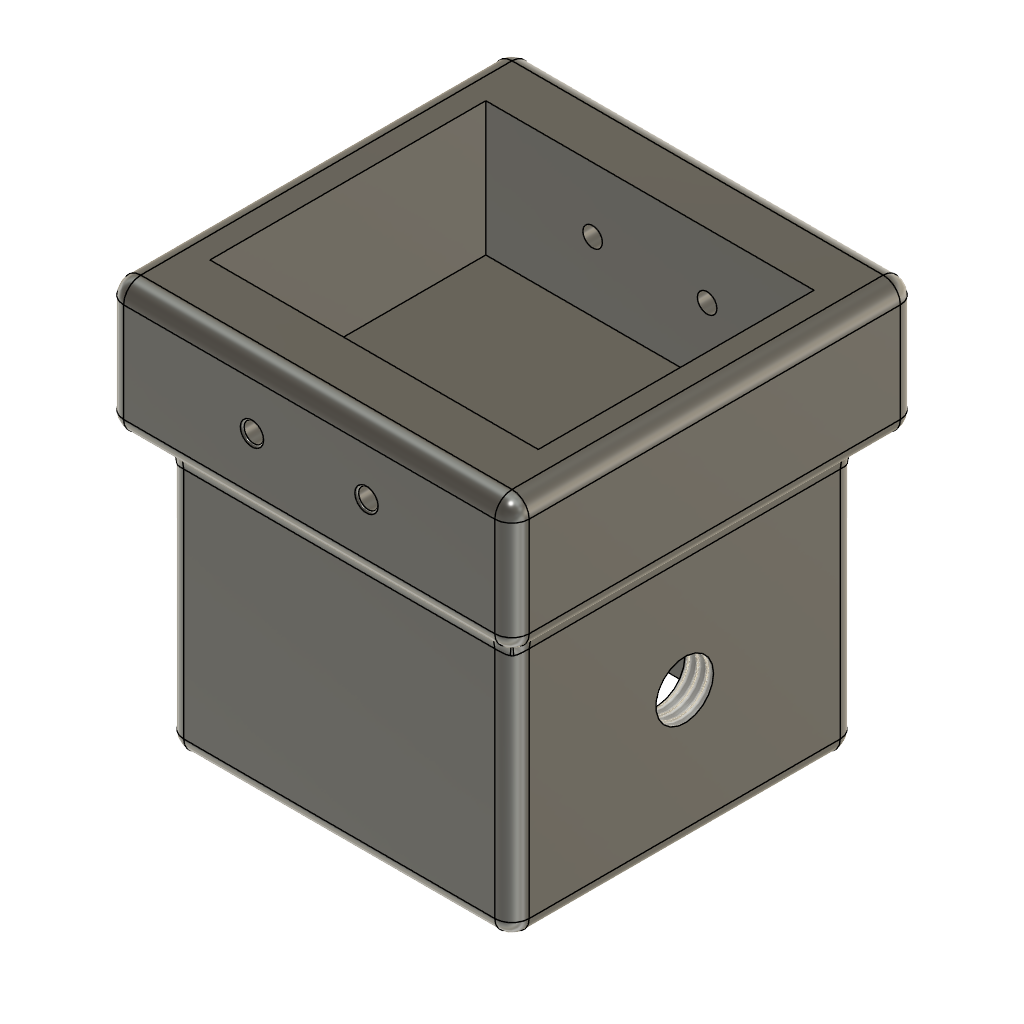
Arm Assembly (Autodesk Fusion 360 archive; units mm, degrees)
design "LongAluEndJoint"
part number: 2026-10-23-13-15-02-691
Autodesk Fusion 360 part; units mm, degrees
sketch "Sketch1" plane through (0, 0, 0) normal (0, 0, 1) x (1, 0, 0)
  line L0 (15.1, -15.1) -> (-15.1, -15.1)
  line L1 (-15.1, -15.1) -> (-15.1, 15.1)
  line L2 (-15.1, 15.1) -> (15.1, 15.1)
  line L3 (15.1, 15.1) -> (15.1, -15.1)
  line L4 (15.1, -15.1) -> (-15.1, 15.1) construction
  line L5 (-15.1, -15.1) -> (15.1, 15.1) construction
  line L6 (-18.1, -18.1) -> (18.1, -18.1)
  line L7 (18.1, -18.1) -> (18.1, 18.1)
  line L8 (18.1, 18.1) -> (-18.1, 18.1)
  line L9 (-18.1, 18.1) -> (-18.1, -18.1)
  line L10 (-18.1, -18.1) -> (18.1, 18.1) construction
  line L11 (18.1, -18.1) -> (-18.1, 18.1) construction
  dimension "d1" = 30.2
  dimension "d2" = 30.2
  dimension "d3" = 36.2
  dimension "d4" = 36.2
  constraint horizontal L0
  constraint perpendicular L0 L1
  constraint parallel L0 L2
  constraint parallel L1 L3
  constraint coincident L4 origin
  constraint coincident L5 origin
  constraint horizontal L6
  constraint perpendicular L6 L7
  constraint parallel L6 L8
  constraint parallel L7 L9
  constraint coincident L10 origin
  constraint coincident L11 origin
  measures "d1" distance of L1.end L2.end
  measures "d2" distance of L0.end L1.end
  measures "d3" distance of L7.end L8.end
  measures "d4" distance of L6.end L7.end
extrude "Extrude1" add sketch "Sketch1" along normal blind 24
sketch "Sketch2" plane through (0, 0, 24) normal (0, 0, 1) x (-1, 0, 0)
  line L0 (15.1, -15.1) -> (-15.1, -15.1)
  line L1 (-15.1, -15.1) -> (-15.1, 15.1)
  line L2 (-15.1, 15.1) -> (15.1, 15.1)
  line L3 (15.1, 15.1) -> (15.1, -15.1)
  line L4 (18.1, -18.1) -> (18.1, 18.1)
  line L5 (18.1, 18.1) -> (-18.1, 18.1)
  line L6 (-18.1, 18.1) -> (-18.1, -18.1)
  line L7 (-18.1, -18.1) -> (18.1, -18.1)
  line L8 (18.1, 18.1) -> (-18.1, 18.1)
  line L9 (-18.1, 18.1) -> (-18.1, -18.1)
  line L10 (-18.1, -18.1) -> (18.1, -18.1)
  line L11 (18.1, -18.1) -> (18.1, 18.1)
  line L12 (18.1, 18.1) -> (-18.1, -18.1) construction
  line L13 (-18.1, 18.1) -> (18.1, -18.1) construction
  dimension "d7" = 36.2
  dimension "d8" = 36.2
  constraint horizontal L8
  constraint perpendicular L8 L9
  constraint parallel L8 L10
  constraint parallel L9 L11
  constraint coincident L12 origin
  constraint coincident L13 origin
  measures "d7" distance of L6.end L4.start
  measures "d8" distance of L5.end L6.end
extrude "Extrude2" add sketch "Sketch2" along normal blind 5 contours L0 L1 L2 L3 | L4 L5 L6 L7 L8 L9 L10 L11
sketch "Sketch3" plane through (0, 0, 29) normal (0, 0, 1) x (-1, 0, 0)
  line L0 (18.1, -18.1) -> (18.1, 18.1)
  line L1 (18.1, 18.1) -> (-18.1, 18.1)
  line L2 (-18.1, 18.1) -> (-18.1, -18.1)
  line L3 (-18.1, -18.1) -> (18.1, -18.1)
  line L4 (-17.2, 14.45) -> (17.2, 14.45)
  line L5 (17.2, 14.45) -> (17.2, -14.45)
  line L6 (17.2, -14.45) -> (-17.2, -14.45)
  line L7 (-17.2, -14.45) -> (-17.2, 14.45)
  line L8 (-17.2, 14.45) -> (17.2, -14.45) construction
  line L9 (17.2, 14.45) -> (-17.2, -14.45) construction
  line L10 (-21.25, 21.25) -> (21.25, 21.25)
  line L11 (21.25, 21.25) -> (21.25, -21.25)
  line L12 (21.25, -21.25) -> (-21.25, -21.25)
  line L13 (-21.25, -21.25) -> (-21.25, 21.25)
  line L14 (-21.25, 21.25) -> (21.25, -21.25) construction
  line L15 (21.25, 21.25) -> (-21.25, -21.25) construction
  dimension "d11" = 34.4
  dimension "d12" = 28.9
  dimension "d13" = 42.5
  dimension "d14" = 42.5
  constraint horizontal L4
  constraint perpendicular L4 L5
  constraint parallel L4 L6
  constraint parallel L5 L7
  constraint coincident L8 origin
  constraint coincident L9 origin
  constraint horizontal L10
  constraint perpendicular L10 L11
  constraint parallel L10 L12
  constraint parallel L11 L13
  constraint coincident L14 origin
  constraint coincident L15 origin
  measures "d11" distance of L5.end L6.end
  measures "d12" distance of L4.end L5.end
  measures "d13" distance of L11.end L12.end
  measures "d14" distance of L10.end L11.end
extrude "Extrude3" add sketch "Sketch3" along normal blind 14 contours L0 L1 L2 L3 | L10 L11 L12 L13
fillet "Fillet1" radius 1.8 20 edges at (-21.25, -21.25, 36) (0, -21.25, 29) (-21.25, 0, 29) (21.25, -21.25, 36) (18.1, -18.1, 14.5) (-18.1, -18.1, 14.5) (-18.1, 18.1, 14.5) (18.1, 18.1, 14.5) (21.25, 0, 29) (0, 21.25, 29) (21.25, 21.25, 36) (-21.25, 21.25, 36) (-21.25, 0, 43) (0, 21.25, 43) (21.25, 0, 43) (0, -21.25, 43) (-18.1, 0, 0) (0, -18.1, 0) (18.1, 0, 0) (0, 18.1, 0)
sketch "Sketch4" plane through (0, -14.45, 0) normal (0, 1, 0) x (-1, 0, 0)
  line L0 (-17.2, 29) -> (17.2, 29)
  line L1 (17.2, 29) -> (17.2, 43)
  line L2 (17.2, 43) -> (-17.2, 43)
  line L3 (-17.2, 43) -> (-17.2, 29)
  circle A0 centre (-6, 36.25) radius 1.025
  line L4 (0, 29) -> (0, 43)
  circle A1 centre (6, 36.25) radius 1.025
  dimension "d21" = 2.05
  dimension "d22" = 7.25
  dimension "d23" = 6
  constraint midpoint L0 L4.start
  constraint midpoint L2 L4.end
  constraint symmetric A0 L4 A1
  measures "d21" diameter of A0
  measures "d22" distance of L0 A0.centre
  measures "d23" distance of A0.centre L4
extrude "Extrude4" cut sketch "Sketch4" against normal through all contours A0 | A1
mirror "Mirror1" about plane through (0, 0, 0) normal (0, 1, 0) of "Extrude4"
sketch "Sketch5" plane through (-18.1, 0, 0) normal (-1, 0, 0) x (0, -1, 0)
  line L0 (16.3, 1.8) -> (16.3, 29)
  line L1 (16.3, 29) -> (-16.3, 29)
  line L2 (-16.3, 29) -> (-16.3, 1.8)
  line L3 (-16.3, 1.8) -> (16.3, 1.8)
  line L4 (0, 29) -> (0, 1.8)
  line L5 (0, 14.4) -> (0, 29)
  line L6 (15.1, 24) -> (-15.1, 24)
  point P0 (0, 14.4)
  dimension "d38" = 9.6
  constraint midpoint L1 L4.start
  constraint midpoint L3 L4.end
  constraint coincident L4 P0
  constraint coincident P0 L5.start
  measures "d38" distance of P0 L6
hole "Hole1" at (-18.1, 0, 14.4) direction (1, 0, 0) diameter 6.036 end through all countersink diameter 6.639 countersink angle 90
thread "Thread1" "ISO Metric profile 7.0 M7x1 M7x1 6H" major diameter 7.1472 minor diameter 6.0355 pitch 1 angle 60 resizes the face on face at (16.1, 0.1504, 17.4142) on face at (-16.899, 0.3005, 17.403)
fillet "Fillet3" radius 3 8 edges at (-17.5728, -17.5728, 29) (0, -18.1, 29) (17.5728, -17.5728, 29) (18.1, 0, 29) (17.5728, 17.5728, 29) (0, 18.1, 29) (-17.5728, 17.5728, 29) (-18.1, 0, 29)
fillet "Fillet4" radius 0.2 4 edges at (6.9556, 21.25, 36.6207) (-5.0444, 21.25, 36.6207) (-5.0444, -21.25, 35.8793) (6.9556, -21.25, 35.8793)

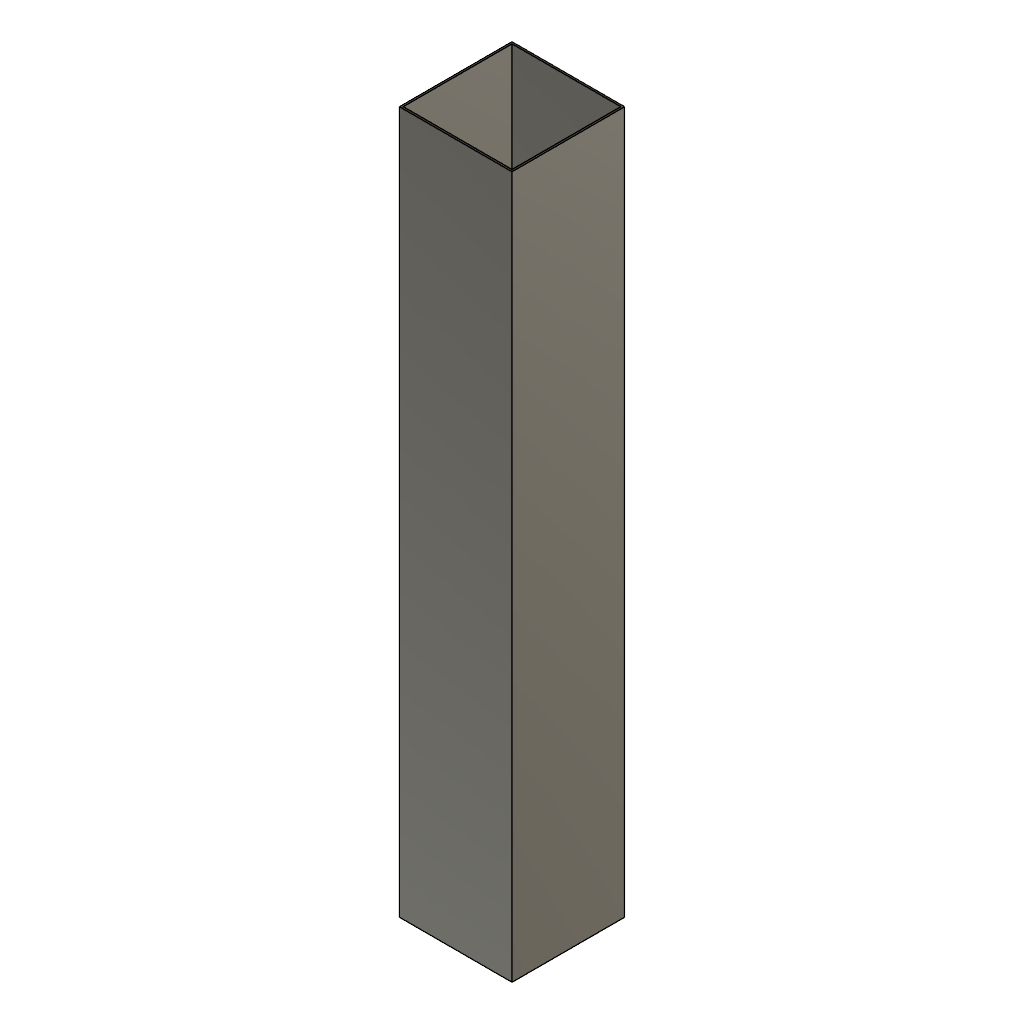
design "ShortAluTube"
part number: 2026-10-26-16-12-56-699
Autodesk Fusion 360 part; units mm, degrees
sketch "Sketch1" plane through (0, 0, 0) normal (0, 0, 1) x (1, 0, 0)
  line L0 (15, -15) -> (-15, -15)
  line L1 (-15, -15) -> (-15, 15)
  line L2 (-15, 15) -> (15, 15)
  line L3 (15, 15) -> (15, -15)
  line L4 (15, -15) -> (-15, 15) construction
  line L5 (-15, -15) -> (15, 15) construction
  line L6 (14.5, -14.5) -> (-14.5, -14.5)
  line L7 (-14.5, -14.5) -> (-14.5, 14.5)
  line L8 (-14.5, 14.5) -> (14.5, 14.5)
  line L9 (14.5, 14.5) -> (14.5, -14.5)
  line L10 (14.5, -14.5) -> (-14.5, 14.5) construction
  line L11 (-14.5, -14.5) -> (14.5, 14.5) construction
  dimension "d1" = 30
  dimension "d2" = 30
  dimension "d3" = 29
  dimension "d4" = 29
  constraint horizontal L0
  constraint perpendicular L0 L1
  constraint parallel L0 L2
  constraint parallel L1 L3
  constraint coincident L4 origin
  constraint coincident L5 origin
  constraint horizontal L6
  constraint perpendicular L6 L7
  constraint parallel L6 L8
  constraint parallel L7 L9
  constraint coincident L10 origin
  constraint coincident L11 origin
  measures "d1" distance of L1.end L2.end
  measures "d2" distance of L0.end L1.end
  measures "d3" distance of L7.end L8.end
  measures "d4" distance of L6.end L7.end
extrude "Extrude1" add sketch "Sketch1" along normal blind 187

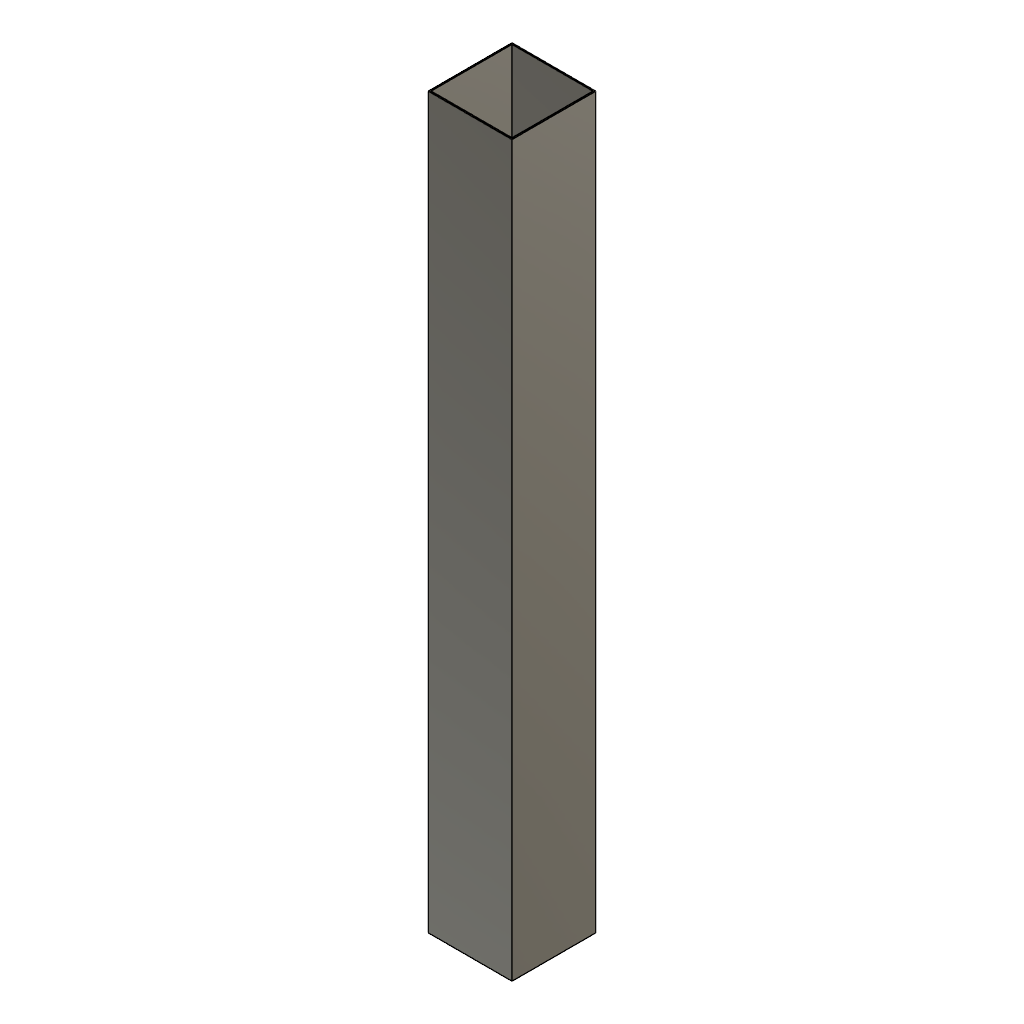
design "LongAluTube"
part number: 2026-10-26-16-12-56-699
Autodesk Fusion 360 part; units mm, degrees
sketch "Sketch1" plane through (0, 0, 0) normal (0, 0, 1) x (1, 0, 0)
  line L0 (15, -15) -> (-15, -15)
  line L1 (-15, -15) -> (-15, 15)
  line L2 (-15, 15) -> (15, 15)
  line L3 (15, 15) -> (15, -15)
  line L4 (15, -15) -> (-15, 15) construction
  line L5 (-15, -15) -> (15, 15) construction
  line L6 (14.5, -14.5) -> (-14.5, -14.5)
  line L7 (-14.5, -14.5) -> (-14.5, 14.5)
  line L8 (-14.5, 14.5) -> (14.5, 14.5)
  line L9 (14.5, 14.5) -> (14.5, -14.5)
  line L10 (14.5, -14.5) -> (-14.5, 14.5) construction
  line L11 (-14.5, -14.5) -> (14.5, 14.5) construction
  dimension "d1" = 30
  dimension "d2" = 30
  dimension "d3" = 29
  dimension "d4" = 29
  constraint horizontal L0
  constraint perpendicular L0 L1
  constraint parallel L0 L2
  constraint parallel L1 L3
  constraint coincident L4 origin
  constraint coincident L5 origin
  constraint horizontal L6
  constraint perpendicular L6 L7
  constraint parallel L6 L8
  constraint parallel L7 L9
  constraint coincident L10 origin
  constraint coincident L11 origin
  measures "d1" distance of L1.end L2.end
  measures "d2" distance of L0.end L1.end
  measures "d3" distance of L7.end L8.end
  measures "d4" distance of L6.end L7.end
extrude "Extrude1" add sketch "Sketch1" along normal blind 261

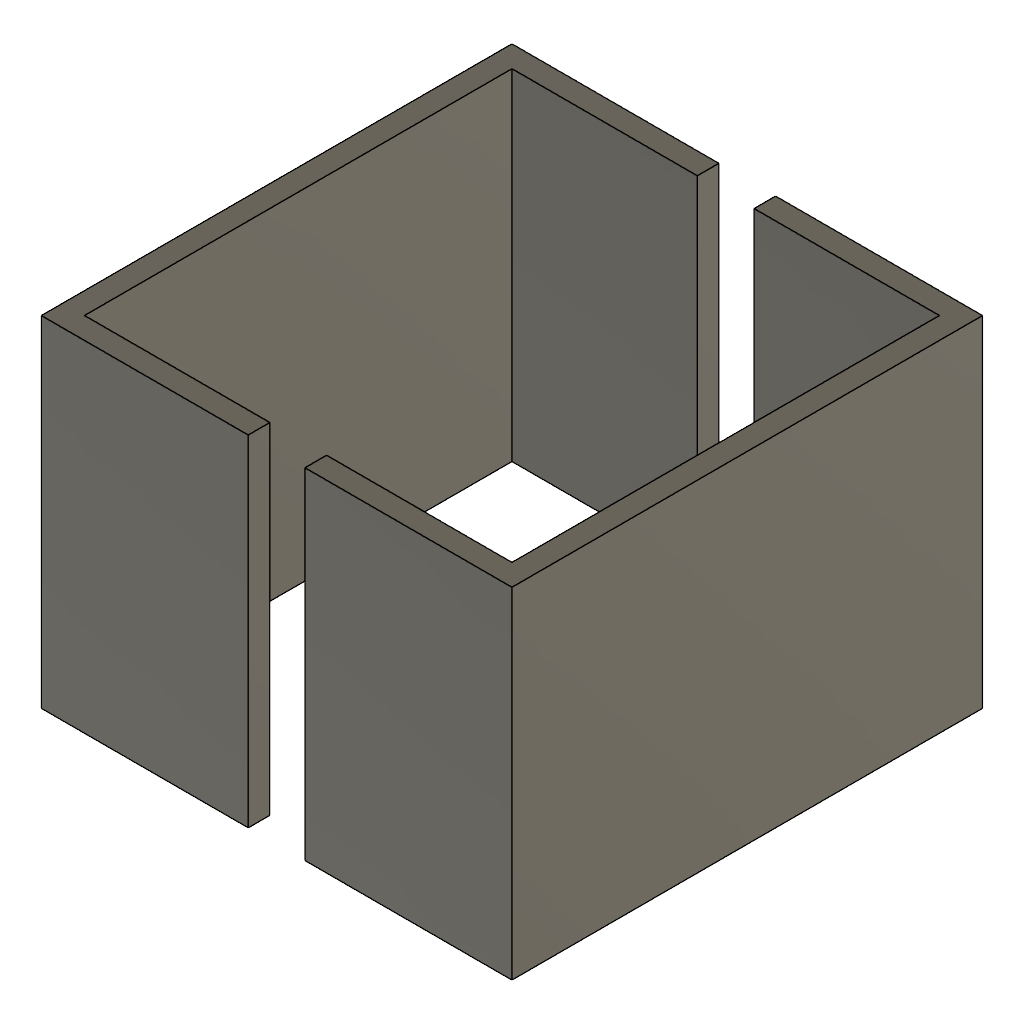
design "ShortAlyEndJointTpuSheet"
part number: 2026-10-28-17-38-30-838
Autodesk Fusion 360 part; units mm, degrees
sketch "Sketch1" plane through (0, 0, 0) normal (0, 0, 1) x (1, 0, 0)
  line L0 (15.075, -15.075) -> (-15.075, -15.075)
  line L1 (-15.075, -15.075) -> (-15.075, 15.075)
  line L2 (-15.075, 15.075) -> (15.075, 15.075)
  line L3 (15.075, 15.075) -> (15.075, -15.075)
  line L4 (15.075, -15.075) -> (-15.075, 15.075) construction
  line L5 (-15.075, -15.075) -> (15.075, 15.075) construction
  line L6 (16.6, -16.6) -> (-16.6, -16.6)
  line L7 (-16.6, -16.6) -> (-16.6, 16.6)
  line L8 (-16.6, 16.6) -> (16.6, 16.6)
  line L9 (16.6, 16.6) -> (16.6, -16.6)
  line L10 (16.6, -16.6) -> (-16.6, 16.6) construction
  line L11 (-16.6, -16.6) -> (16.6, 16.6) construction
  dimension "d1" = 30.15
  dimension "d2" = 30.15
  dimension "d3" = 33.2
  dimension "d4" = 33.2
  constraint horizontal L0
  constraint perpendicular L0 L1
  constraint parallel L0 L2
  constraint parallel L1 L3
  constraint coincident L4 origin
  constraint coincident L5 origin
  constraint horizontal L6
  constraint perpendicular L6 L7
  constraint parallel L6 L8
  constraint parallel L7 L9
  constraint coincident L10 origin
  constraint coincident L11 origin
  measures "d1" distance of L1.end L2.end
  measures "d2" distance of L0.end L1.end
  measures "d3" distance of L7.end L8.end
  measures "d4" distance of L6.end L7.end
extrude "Extrude1" add sketch "Sketch1" along normal blind 24 makes body 1
sketch "Sketch2" plane through (0, -16.6, 0) normal (0, -1, 0) x (1, 0, 0)
  line L0 (-16.6, 0) -> (16.6, 0)
  line L1 (16.6, 0) -> (16.6, 24)
  line L2 (16.6, 24) -> (-16.6, 24)
  line L3 (-16.6, 24) -> (-16.6, 0)
  line L4 (2, 24) -> (-2, 24)
  line L5 (-2, 24) -> (-2, -24)
  line L6 (-2, -24) -> (2, -24)
  line L7 (2, -24) -> (2, 24)
  line L8 (2, 24) -> (-2, -24) construction
  line L9 (-2, 24) -> (2, -24) construction
  dimension "d7" = 4
  dimension "d8" = 48
  constraint horizontal L4
  constraint perpendicular L4 L5
  constraint parallel L4 L6
  constraint parallel L5 L7
  constraint coincident L8 origin
  constraint coincident L9 origin
  measures "d7" distance of L5.end L6.end
  measures "d8" distance of L4.end L5.end
extrude "Extrude2" cut sketch "Sketch2" against normal through all contours L0 L2 L4 L5 L7 bodies 1 makes body 2 at (16.6, -5.5333, 16)
